Autodesk Fusion 360 part; units mm, degrees
(part 2 of 7)
sketch "Editable cross section (98)" plane through (0, 0, 0) normal (0, 0, 1) x (1, 0, 0) in component "left scoring bearing bridge 33"
  line L0 (-7.5, -5) -> (7.5, -5)
  line L1 (7.5, -5) -> (7.5, 5)
  line L2 (7.5, 5) -> (-7.5, 5)
  line L3 (-7.5, 5) -> (-7.5, -5)
extrude "Stock length''''''''''''''''''''''''''''''''''''''''''''''''''''''''''''''''''''''''''''" add sketch "Editable cross section (98)" along normal blind 42 separate body makes body 77 in component "left scoring bearing bridge 33"
sketch "Editable cross section (99)" plane through (0, 0, 0) normal (0, 0, 1) x (1, 0, 0) in component "left feed diverter pivot"
  circle A0 centre (0, 0) radius 7
extrude "Stock length'''''''''''''''''''''''''''''''''''''''''''''''''''''''''''''''''''''''''''''" add sketch "Editable cross section (99)" along normal blind 24 separate body makes body 78 in component "left feed diverter pivot"
sketch "Editable cross section (100)" plane through (0, 0, 0) normal (0, 0, 1) x (1, 0, 0) in component "right feed diverter pivot"
  circle A0 centre (0, 0) radius 7
extrude "Stock length''''''''''''''''''''''''''''''''''''''''''''''''''''''''''''''''''''''''''''''" add sketch "Editable cross section (100)" along normal blind 24 separate body makes body 79 in component "right feed diverter pivot"
sketch "Editable cross section (101)" plane through (0, 0, 0) normal (0, 0, 1) x (1, 0, 0) in component "feed diverter vane"
  line L0 (-2, -75) -> (2, -75)
  line L1 (2, -75) -> (2, 75)
  line L2 (2, 75) -> (-2, 75)
  line L3 (-2, 75) -> (-2, -75)
extrude "Stock length'''''''''''''''''''''''''''''''''''''''''''''''''''''''''''''''''''''''''''''''" add sketch "Editable cross section (101)" along normal blind 46 separate body makes body 80 in component "feed diverter vane"
sketch "Editable cross section (102)" plane through (0, 0, 0) normal (0, 0, 1) x (1, 0, 0) in component "front left public wheel"
  circle A0 centre (0, 0) radius 38.1
sketch "Editable cross section (103)" plane through (0, 0, 0) normal (0, 0, 1) x (1, 0, 0) in component "front left public drive housing"
  line L0 (-40, -40) -> (40, -40)
  line L1 (40, -40) -> (40, 40)
  line L2 (40, 40) -> (-40, 40)
  line L3 (-40, 40) -> (-40, -40)
sketch "Editable cross section (104)" plane through (0, 0, 0) normal (0, 0, 1) x (1, 0, 0) in component "front left public motor reserve"
  circle A0 centre (0, 0) radius 29.9
sketch "Editable cross section (105)" plane through (0, 0, 0) normal (0, 0, 1) x (1, 0, 0) in component "front right public wheel"
  circle A0 centre (0, 0) radius 38.1
sketch "Editable cross section (106)" plane through (0, 0, 0) normal (0, 0, 1) x (1, 0, 0) in component "front right public drive housing"
  line L0 (-40, -40) -> (40, -40)
  line L1 (40, -40) -> (40, 40)
  line L2 (40, 40) -> (-40, 40)
  line L3 (-40, 40) -> (-40, -40)
sketch "Editable cross section (107)" plane through (0, 0, 0) normal (0, 0, 1) x (1, 0, 0) in component "front right public motor reserve"
  circle A0 centre (0, 0) radius 29.9
sketch "Editable cross section (108)" plane through (0, 0, 0) normal (0, 0, 1) x (1, 0, 0) in component "rear left public wheel"
  circle A0 centre (0, 0) radius 38.1
sketch "Editable cross section (109)" plane through (0, 0, 0) normal (0, 0, 1) x (1, 0, 0) in component "rear left public drive housing"
  line L0 (-40, -40) -> (40, -40)
  line L1 (40, -40) -> (40, 40)
  line L2 (40, 40) -> (-40, 40)
  line L3 (-40, 40) -> (-40, -40)
sketch "Editable cross section (110)" plane through (0, 0, 0) normal (0, 0, 1) x (1, 0, 0) in component "rear left public motor reserve"
  circle A0 centre (0, 0) radius 29.9
sketch "Editable cross section (111)" plane through (0, 0, 0) normal (0, 0, 1) x (1, 0, 0) in component "rear right public wheel"
  circle A0 centre (0, 0) radius 38.1
sketch "Editable cross section (112)" plane through (0, 0, 0) normal (0, 0, 1) x (1, 0, 0) in component "rear right public drive housing"
  line L0 (-40, -40) -> (40, -40)
  line L1 (40, -40) -> (40, 40)
  line L2 (40, 40) -> (-40, 40)
  line L3 (-40, 40) -> (-40, -40)
sketch "Editable cross section (113)" plane through (0, 0, 0) normal (0, 0, 1) x (1, 0, 0) in component "rear right public motor reserve"
  circle A0 centre (0, 0) radius 29.9
sketch "Editable cross section (114)" plane through (0, 0, 0) normal (0, 0, 1) x (1, 0, 0) in component "right public scoring motor envelope"
  circle A0 centre (0, 0) radius 30
extrude "Stock length''''''''''''''''''''''''''''''''''''''''''''''''''''''''''''''''''''''''''''''''" add sketch "Editable cross section (114)" along normal blind 93.26 separate body makes body 81 in component "right public scoring motor envelope"
sketch "Editable cross section (115)" plane through (0, 0, 0) normal (0, 0, 1) x (1, 0, 0) in component "left public scoring motor envelope"
  circle A0 centre (0, 0) radius 30
extrude "Stock length'''''''''''''''''''''''''''''''''''''''''''''''''''''''''''''''''''''''''''''''''" add sketch "Editable cross section (115)" along normal blind 93.26 separate body makes body 82 in component "left public scoring motor envelope"
sketch "Editable cross section (116)" plane through (0, 0, 0) normal (0, 0, 1) x (1, 0, 0) in component "rear lift custody gate"
  line L0 (-2, -65) -> (2, -65)
  line L1 (2, -65) -> (2, 65)
  line L2 (2, 65) -> (-2, 65)
  line L3 (-2, 65) -> (-2, -65)
extrude "Stock length''''''''''''''''''''''''''''''''''''''''''''''''''''''''''''''''''''''''''''''''''" add sketch "Editable cross section (116)" along normal blind 416 separate body makes body 83 in component "rear lift custody gate"
sketch "Editable cross section (117)" plane through (0, 0, 0) normal (0, 0, 1) x (1, 0, 0) in component "front lift custody guide"
  line L0 (-2, -65) -> (2, -65)
  line L1 (2, -65) -> (2, 65)
  line L2 (2, 65) -> (-2, 65)
  line L3 (-2, 65) -> (-2, -65)
extrude "Stock length'''''''''''''''''''''''''''''''''''''''''''''''''''''''''''''''''''''''''''''''''''" add sketch "Editable cross section (117)" along normal blind 361 separate body makes body 84 in component "front lift custody guide"
sketch "Editable cross section (118)" plane through (0, 0, 0) normal (0, 0, 1) x (1, 0, 0) in component "left mast"
  line L0 (-10, -10) -> (10, -10)
  line L1 (10, -10) -> (10, 10)
  line L2 (10, 10) -> (-10, 10)
  line L3 (-10, 10) -> (-10, -10)
  line L4 (-8, -8) -> (8, -8)
  line L5 (8, -8) -> (8, 8)
  line L6 (8, 8) -> (-8, 8)
  line L7 (-8, 8) -> (-8, -8)
extrude "Stock length''''''''''''''''''''''''''''''''''''''''''''''''''''''''''''''''''''''''''''''''''''" add sketch "Editable cross section (118)" along normal blind 629.2 separate body makes body 85 in component "left mast"
sketch "Editable cross section (119)" plane through (0, 0, 0) normal (0, 0, 1) x (1, 0, 0) in component "left aft mast"
  line L0 (-10, -10) -> (10, -10)
  line L1 (10, -10) -> (10, 10)
  line L2 (10, 10) -> (-10, 10)
  line L3 (-10, 10) -> (-10, -10)
  line L4 (-8, -8) -> (8, -8)
  line L5 (8, -8) -> (8, 8)
  line L6 (8, 8) -> (-8, 8)
  line L7 (-8, 8) -> (-8, -8)
extrude "Stock length'''''''''''''''''''''''''''''''''''''''''''''''''''''''''''''''''''''''''''''''''''''" add sketch "Editable cross section (119)" along normal blind 629.2 separate body makes body 86 in component "left aft mast"
sketch "Editable cross section (120)" plane through (0, 0, 0) normal (0, 0, 1) x (1, 0, 0) in component "left upper bearing plate"
  line L0 (-64, -19) -> (64, -19)
  line L1 (64, -19) -> (64, 19)
  line L2 (64, 19) -> (-64, 19)
  line L3 (-64, 19) -> (-64, -19)
extrude "Stock length''''''''''''''''''''''''''''''''''''''''''''''''''''''''''''''''''''''''''''''''''''''" add sketch "Editable cross section (120)" along normal blind 6 separate body makes body 87 in component "left upper bearing plate"
sketch "Editable cross section (121)" plane through (0, 0, 0) normal (0, 0, 1) x (1, 0, 0) in component "left lower bearing plate"
  line L0 (-27, -21.5) -> (27, -21.5)
  line L1 (27, -21.5) -> (27, 21.5)
  line L2 (27, 21.5) -> (-27, 21.5)
  line L3 (-27, 21.5) -> (-27, -21.5)
extrude "Stock length'''''''''''''''''''''''''''''''''''''''''''''''''''''''''''''''''''''''''''''''''''''''" add sketch "Editable cross section (121)" along normal blind 6 separate body makes body 88 in component "left lower bearing plate"
sketch "Editable cross section (122)" plane through (0, 0, 0) normal (0, 0, 1) x (1, 0, 0) in component "left lead screw envelope"
  circle A0 centre (0, 0) radius 5
extrude "Stock length''''''''''''''''''''''''''''''''''''''''''''''''''''''''''''''''''''''''''''''''''''''''" add sketch "Editable cross section (122)" along normal blind 187 separate body makes body 89 in component "left lead screw envelope"
sketch "Editable cross section (123)" plane through (0, 0, 0) normal (0, 0, 1) x (1, 0, 0) in component "left lift motor envelope"
  circle A0 centre (0, 0) radius 30
extrude "Stock length'''''''''''''''''''''''''''''''''''''''''''''''''''''''''''''''''''''''''''''''''''''''''" add sketch "Editable cross section (123)" along normal blind 61 separate body makes body 90 in component "left lift motor envelope"
sketch "Editable cross section (124)" plane through (0, 0, 0) normal (0, 0, 1) x (1, 0, 0) in component "left reduction envelope"
  line L0 (-19, -32) -> (19, -32)
  line L1 (19, -32) -> (19, 32)
  line L2 (19, 32) -> (-19, 32)
  line L3 (-19, 32) -> (-19, -32)
extrude "Stock length''''''''''''''''''''''''''''''''''''''''''''''''''''''''''''''''''''''''''''''''''''''''''" add sketch "Editable cross section (124)" along normal blind 20 separate body makes body 91 in component "left reduction envelope"
sketch "Editable cross section (125)" plane through (0, 0, 0) normal (0, 0, 1) x (1, 0, 0) in component "left driven nut"
  line L0 (-9, -9.5) -> (9, -9.5)
  line L1 (9, -9.5) -> (9, 9.5)
  line L2 (9, 9.5) -> (-9, 9.5)
  line L3 (-9, 9.5) -> (-9, -9.5)
  circle A0 centre (0, -0.5) radius 5
extrude "Stock length'''''''''''''''''''''''''''''''''''''''''''''''''''''''''''''''''''''''''''''''''''''''''''" add sketch "Editable cross section (125)" along normal blind 14 separate body makes body 92 in component "left driven nut"
sketch "Editable cross section (126)" plane through (0, 0, 0) normal (0, 0, 1) x (1, 0, 0) in component "left nut link"
  line L0 (-8, -8) -> (8, -8)
  line L1 (8, -8) -> (8, 8)
  line L2 (8, 8) -> (-8, 8)
  line L3 (-8, 8) -> (-8, -8)
  circle A0 centre (0, -1) radius 5.8
extrude "Stock length''''''''''''''''''''''''''''''''''''''''''''''''''''''''''''''''''''''''''''''''''''''''''''" add sketch "Editable cross section (126)" along normal blind 10 separate body makes body 93 in component "left nut link"
sketch "Editable cross section (127)" plane through (0, 0, 0) normal (0, 0, 1) x (1, 0, 0) in component "left crosshead cheek"
  line L0 (-87.5, -11.5) -> (87.5, -11.5)
  line L1 (87.5, -11.5) -> (87.5, 11.5)
  line L2 (87.5, 11.5) -> (-87.5, 11.5)
  line L3 (-87.5, 11.5) -> (-87.5, -11.5)
  circle A0 centre (-35.5, 1.5) radius 5.8
extrude "Stock length'''''''''''''''''''''''''''''''''''''''''''''''''''''''''''''''''''''''''''''''''''''''''''''" add sketch "Editable cross section (127)" along normal blind 14 separate body makes body 94 in component "left crosshead cheek"
sketch "Editable cross section (128)" plane through (0, 0, 0) normal (0, 0, 1) x (1, 0, 0) in component "left forward carriage sleeve"
  line L0 (-13, -12.5) -> (13, -12.5)
  line L1 (13, -12.5) -> (13, 12.5)
  line L2 (13, 12.5) -> (-13, 12.5)
  line L3 (-13, 12.5) -> (-13, -12.5)
  line L4 (-11, -10.5) -> (11, -10.5)
  line L5 (11, -10.5) -> (11, 10.5)
  line L6 (11, 10.5) -> (-11, 10.5)
  line L7 (-11, 10.5) -> (-11, -10.5)
extrude "Stock length''''''''''''''''''''''''''''''''''''''''''''''''''''''''''''''''''''''''''''''''''''''''''''''" add sketch "Editable cross section (128)" along normal blind 40 separate body makes body 95 in component "left forward carriage sleeve"
sketch "Editable cross section (129)" plane through (0, 0, 0) normal (0, 0, 1) x (1, 0, 0) in component "left aft carriage sleeve"
  line L0 (-13, -12.5) -> (13, -12.5)
  line L1 (13, -12.5) -> (13, 12.5)
  line L2 (13, 12.5) -> (-13, 12.5)
  line L3 (-13, 12.5) -> (-13, -12.5)
  line L4 (-11, -10.5) -> (11, -10.5)
  line L5 (11, -10.5) -> (11, 10.5)
  line L6 (11, 10.5) -> (-11, 10.5)
  line L7 (-11, 10.5) -> (-11, -10.5)
extrude "Stock length'''''''''''''''''''''''''''''''''''''''''''''''''''''''''''''''''''''''''''''''''''''''''''''''" add sketch "Editable cross section (129)" along normal blind 40 separate body makes body 96 in component "left aft carriage sleeve"
sketch "Editable cross section (130)" plane through (0, 0, 0) normal (0, 0, 1) x (1, 0, 0) in component "left extension sleeve"
  line L0 (-14, -15) -> (14, -15)
  line L1 (14, -15) -> (14, 15)
  line L2 (14, 15) -> (-14, 15)
  line L3 (-14, 15) -> (-14, -15)
  line L4 (-12, -13) -> (12, -13)
  line L5 (12, -13) -> (12, 13)
  line L6 (12, 13) -> (-12, 13)
  line L7 (-12, 13) -> (-12, -13)
extrude "Stock length''''''''''''''''''''''''''''''''''''''''''''''''''''''''''''''''''''''''''''''''''''''''''''''''" add sketch "Editable cross section (130)" along normal blind 87 separate body makes body 97 in component "left extension sleeve"
sketch "Editable cross section (131)" plane through (0, 0, 0) normal (0, 0, 1) x (1, 0, 0) in component "left sleeve pedestal"
  line L0 (-11, -11) -> (11, -11)
  line L1 (11, -11) -> (11, 11)
  line L2 (11, 11) -> (-11, 11)
  line L3 (-11, 11) -> (-11, -11)
extrude "Stock length'''''''''''''''''''''''''''''''''''''''''''''''''''''''''''''''''''''''''''''''''''''''''''''''''" add sketch "Editable cross section (131)" along normal blind 23 separate body makes body 98 in component "left sleeve pedestal"
sketch "Editable cross section (132)" plane through (0, 0, 0) normal (0, 0, 1) x (1, 0, 0) in component "left extending rail"
  line L0 (-10, -11) -> (10, -11)
  line L1 (10, -11) -> (10, 11)
  line L2 (10, 11) -> (-10, 11)
  line L3 (-10, 11) -> (-10, -11)
  line L4 (-8, -9) -> (8, -9)
  line L5 (8, -9) -> (8, 9)
  line L6 (8, 9) -> (-8, 9)
  line L7 (-8, 9) -> (-8, -9)
extrude "Stock length''''''''''''''''''''''''''''''''''''''''''''''''''''''''''''''''''''''''''''''''''''''''''''''''''" add sketch "Editable cross section (132)" along normal blind 395 separate body makes body 99 in component "left extending rail"
sketch "Low-rung crown and capture slot" plane through (0, 0, 0) normal (0, 0, 1) x (1, 0, 0) in component "left crown hook"
  line L0 (-283, 710) -> (-271, 710)
  line L1 (-271, 710) -> (-271, 737)
  line L2 (-271, 737) -> (-223, 737)
  line L3 (-223, 737) -> (-223, 710)
  line L4 (-223, 710) -> (-211, 710)
  line L5 (-211, 710) -> (-211, 736)
  line L6 (-211, 736) -> (-176, 736)
  line L7 (-176, 736) -> (-176, 753)
  line L8 (-176, 753) -> (-283, 753)
  line L9 (-283, 753) -> (-283, 710)
extrude "Hook plate thickness" add sketch "Low-rung crown and capture slot" along normal blind 12 separate body makes body 100 in component "left crown hook"
sketch "Editable cross section (133)" plane through (0, 0, 0) normal (0, 0, 1) x (1, 0, 0) in component "right mast"
  line L0 (-10, -10) -> (10, -10)
  line L1 (10, -10) -> (10, 10)
  line L2 (10, 10) -> (-10, 10)
  line L3 (-10, 10) -> (-10, -10)
  line L4 (-8, -8) -> (8, -8)
  line L5 (8, -8) -> (8, 8)
  line L6 (8, 8) -> (-8, 8)
  line L7 (-8, 8) -> (-8, -8)
extrude "Stock length'''''''''''''''''''''''''''''''''''''''''''''''''''''''''''''''''''''''''''''''''''''''''''''''''''" add sketch "Editable cross section (133)" along normal blind 629.2 separate body makes body 101 in component "right mast"
sketch "Editable cross section (134)" plane through (0, 0, 0) normal (0, 0, 1) x (1, 0, 0) in component "right aft mast"
  line L0 (-10, -10) -> (10, -10)
  line L1 (10, -10) -> (10, 10)
  line L2 (10, 10) -> (-10, 10)
  line L3 (-10, 10) -> (-10, -10)
  line L4 (-8, -8) -> (8, -8)
  line L5 (8, -8) -> (8, 8)
  line L6 (8, 8) -> (-8, 8)
  line L7 (-8, 8) -> (-8, -8)
extrude "Stock length''''''''''''''''''''''''''''''''''''''''''''''''''''''''''''''''''''''''''''''''''''''''''''''''''''" add sketch "Editable cross section (134)" along normal blind 629.2 separate body makes body 102 in component "right aft mast"
sketch "Editable cross section (135)" plane through (0, 0, 0) normal (0, 0, 1) x (1, 0, 0) in component "right upper bearing plate"
  line L0 (-64, -19) -> (64, -19)
  line L1 (64, -19) -> (64, 19)
  line L2 (64, 19) -> (-64, 19)
  line L3 (-64, 19) -> (-64, -19)
extrude "Stock length'''''''''''''''''''''''''''''''''''''''''''''''''''''''''''''''''''''''''''''''''''''''''''''''''''''" add sketch "Editable cross section (135)" along normal blind 6 separate body makes body 103 in component "right upper bearing plate"
sketch "Editable cross section (136)" plane through (0, 0, 0) normal (0, 0, 1) x (1, 0, 0) in component "right lower bearing plate"
  line L0 (-27, -21.5) -> (27, -21.5)
  line L1 (27, -21.5) -> (27, 21.5)
  line L2 (27, 21.5) -> (-27, 21.5)
  line L3 (-27, 21.5) -> (-27, -21.5)
extrude "Stock length''''''''''''''''''''''''''''''''''''''''''''''''''''''''''''''''''''''''''''''''''''''''''''''''''''''" add sketch "Editable cross section (136)" along normal blind 6 separate body makes body 104 in component "right lower bearing plate"
sketch "Editable cross section (137)" plane through (0, 0, 0) normal (0, 0, 1) x (1, 0, 0) in component "right lead screw envelope"
  circle A0 centre (0, 0) radius 5
extrude "Stock length'''''''''''''''''''''''''''''''''''''''''''''''''''''''''''''''''''''''''''''''''''''''''''''''''''''''" add sketch "Editable cross section (137)" along normal blind 187 separate body makes body 105 in component "right lead screw envelope"
sketch "Editable cross section (138)" plane through (0, 0, 0) normal (0, 0, 1) x (1, 0, 0) in component "right lift motor envelope"
  circle A0 centre (0, 0) radius 30
extrude "Stock length''''''''''''''''''''''''''''''''''''''''''''''''''''''''''''''''''''''''''''''''''''''''''''''''''''''''" add sketch "Editable cross section (138)" along normal blind 61 separate body makes body 106 in component "right lift motor envelope"
sketch "Editable cross section (139)" plane through (0, 0, 0) normal (0, 0, 1) x (1, 0, 0) in component "right reduction envelope"
  line L0 (-19, -32) -> (19, -32)
  line L1 (19, -32) -> (19, 32)
  line L2 (19, 32) -> (-19, 32)
  line L3 (-19, 32) -> (-19, -32)
extrude "Stock length'''''''''''''''''''''''''''''''''''''''''''''''''''''''''''''''''''''''''''''''''''''''''''''''''''''''''" add sketch "Editable cross section (139)" along normal blind 20 separate body makes body 107 in component "right reduction envelope"
sketch "Editable cross section (140)" plane through (0, 0, 0) normal (0, 0, 1) x (1, 0, 0) in component "right driven nut"
  line L0 (-9, -9.5) -> (9, -9.5)
  line L1 (9, -9.5) -> (9, 9.5)
  line L2 (9, 9.5) -> (-9, 9.5)
  line L3 (-9, 9.5) -> (-9, -9.5)
  circle A0 centre (0, 0.5) radius 5
extrude "Stock length''''''''''''''''''''''''''''''''''''''''''''''''''''''''''''''''''''''''''''''''''''''''''''''''''''''''''" add sketch "Editable cross section (140)" along normal blind 14 separate body makes body 108 in component "right driven nut"
sketch "Editable cross section (141)" plane through (0, 0, 0) normal (0, 0, 1) x (1, 0, 0) in component "right nut link"
  line L0 (-8, -8) -> (8, -8)
  line L1 (8, -8) -> (8, 8)
  line L2 (8, 8) -> (-8, 8)
  line L3 (-8, 8) -> (-8, -8)
  circle A0 centre (0, 1) radius 5.8
extrude "Stock length'''''''''''''''''''''''''''''''''''''''''''''''''''''''''''''''''''''''''''''''''''''''''''''''''''''''''''" add sketch "Editable cross section (141)" along normal blind 10 separate body makes body 109 in component "right nut link"
sketch "Editable cross section (142)" plane through (0, 0, 0) normal (0, 0, 1) x (1, 0, 0) in component "right crosshead cheek"
  line L0 (-87.5, -11.5) -> (87.5, -11.5)
  line L1 (87.5, -11.5) -> (87.5, 11.5)
  line L2 (87.5, 11.5) -> (-87.5, 11.5)
  line L3 (-87.5, 11.5) -> (-87.5, -11.5)
  circle A0 centre (-35.5, -1.5) radius 5.8
extrude "Stock length''''''''''''''''''''''''''''''''''''''''''''''''''''''''''''''''''''''''''''''''''''''''''''''''''''''''''''" add sketch "Editable cross section (142)" along normal blind 14 separate body makes body 110 in component "right crosshead cheek"
sketch "Editable cross section (143)" plane through (0, 0, 0) normal (0, 0, 1) x (1, 0, 0) in component "right forward carriage sleeve"
  line L0 (-13, -12.5) -> (13, -12.5)
  line L1 (13, -12.5) -> (13, 12.5)
  line L2 (13, 12.5) -> (-13, 12.5)
  line L3 (-13, 12.5) -> (-13, -12.5)
  line L4 (-11, -10.5) -> (11, -10.5)
  line L5 (11, -10.5) -> (11, 10.5)
  line L6 (11, 10.5) -> (-11, 10.5)
  line L7 (-11, 10.5) -> (-11, -10.5)
extrude "Stock length'''''''''''''''''''''''''''''''''''''''''''''''''''''''''''''''''''''''''''''''''''''''''''''''''''''''''''''" add sketch "Editable cross section (143)" along normal blind 40 separate body makes body 111 in component "right forward carriage sleeve"
sketch "Editable cross section (144)" plane through (0, 0, 0) normal (0, 0, 1) x (1, 0, 0) in component "right aft carriage sleeve"
  line L0 (-13, -12.5) -> (13, -12.5)
  line L1 (13, -12.5) -> (13, 12.5)
  line L2 (13, 12.5) -> (-13, 12.5)
  line L3 (-13, 12.5) -> (-13, -12.5)
  line L4 (-11, -10.5) -> (11, -10.5)
  line L5 (11, -10.5) -> (11, 10.5)
  line L6 (11, 10.5) -> (-11, 10.5)
  line L7 (-11, 10.5) -> (-11, -10.5)
extrude "Stock length''''''''''''''''''''''''''''''''''''''''''''''''''''''''''''''''''''''''''''''''''''''''''''''''''''''''''''''" add sketch "Editable cross section (144)" along normal blind 40 separate body makes body 112 in component "right aft carriage sleeve"
sketch "Editable cross section (145)" plane through (0, 0, 0) normal (0, 0, 1) x (1, 0, 0) in component "right extension sleeve"
  line L0 (-14, -15) -> (14, -15)
  line L1 (14, -15) -> (14, 15)
  line L2 (14, 15) -> (-14, 15)
  line L3 (-14, 15) -> (-14, -15)
  line L4 (-12, -13) -> (12, -13)
  line L5 (12, -13) -> (12, 13)
  line L6 (12, 13) -> (-12, 13)
  line L7 (-12, 13) -> (-12, -13)
extrude "Stock length'''''''''''''''''''''''''''''''''''''''''''''''''''''''''''''''''''''''''''''''''''''''''''''''''''''''''''''''" add sketch "Editable cross section (145)" along normal blind 87 separate body makes body 113 in component "right extension sleeve"
sketch "Editable cross section (146)" plane through (0, 0, 0) normal (0, 0, 1) x (1, 0, 0) in component "right sleeve pedestal"
  line L0 (-11, -11) -> (11, -11)
  line L1 (11, -11) -> (11, 11)
  line L2 (11, 11) -> (-11, 11)
  line L3 (-11, 11) -> (-11, -11)
extrude "Stock length''''''''''''''''''''''''''''''''''''''''''''''''''''''''''''''''''''''''''''''''''''''''''''''''''''''''''''''''" add sketch "Editable cross section (146)" along normal blind 23 separate body makes body 114 in component "right sleeve pedestal"
sketch "Editable cross section (147)" plane through (0, 0, 0) normal (0, 0, 1) x (1, 0, 0) in component "right extending rail"
  line L0 (-10, -11) -> (10, -11)
  line L1 (10, -11) -> (10, 11)
  line L2 (10, 11) -> (-10, 11)
  line L3 (-10, 11) -> (-10, -11)
  line L4 (-8, -9) -> (8, -9)
  line L5 (8, -9) -> (8, 9)
  line L6 (8, 9) -> (-8, 9)
  line L7 (-8, 9) -> (-8, -9)
extrude "Stock length'''''''''''''''''''''''''''''''''''''''''''''''''''''''''''''''''''''''''''''''''''''''''''''''''''''''''''''''''" add sketch "Editable cross section (147)" along normal blind 395 separate body makes body 115 in component "right extending rail"
sketch "Low-rung crown and capture slot (2)" plane through (0, 0, 0) normal (0, 0, 1) x (1, 0, 0) in component "right crown hook"
  line L0 (-283, 710) -> (-271, 710)
  line L1 (-271, 710) -> (-271, 737)
  line L2 (-271, 737) -> (-223, 737)
  line L3 (-223, 737) -> (-223, 710)
  line L4 (-223, 710) -> (-211, 710)
  line L5 (-211, 710) -> (-211, 736)
  line L6 (-211, 736) -> (-176, 736)
  line L7 (-176, 736) -> (-176, 753)
  line L8 (-176, 753) -> (-283, 753)
  line L9 (-283, 753) -> (-283, 710)
extrude "Hook plate thickness'" add sketch "Low-rung crown and capture slot (2)" along normal blind 12 separate body makes body 116 in component "right crown hook"
sketch "Editable cross section (148)" plane through (0, 0, 0) normal (0, 0, 1) x (1, 0, 0) in component "crosshead lift bridge"
  line L0 (-10, -10) -> (10, -10)
  line L1 (10, -10) -> (10, 10)
  line L2 (10, 10) -> (-10, 10)
  line L3 (-10, 10) -> (-10, -10)
  line L4 (-8, -8) -> (8, -8)
  line L5 (8, -8) -> (8, 8)
  line L6 (8, 8) -> (-8, 8)
  line L7 (-8, 8) -> (-8, -8)
extrude "Stock length''''''''''''''''''''''''''''''''''''''''''''''''''''''''''''''''''''''''''''''''''''''''''''''''''''''''''''''''''" add sketch "Editable cross section (148)" along normal blind 630 separate body makes body 117 in component "crosshead lift bridge"
sketch "Editable cross section (149)" plane through (0, 0, 0) normal (0, 0, 1) x (1, 0, 0) in component "rail synchronizing tie"
  line L0 (-10, -82) -> (10, -82)
  line L1 (10, -82) -> (10, 82)
  line L2 (10, 82) -> (-10, 82)
  line L3 (-10, 82) -> (-10, -82)
extrude "Stock length'''''''''''''''''''''''''''''''''''''''''''''''''''''''''''''''''''''''''''''''''''''''''''''''''''''''''''''''''''" add sketch "Editable cross section (149)" along normal blind 4 separate body makes body 118 in component "rail synchronizing tie"
sketch "Editable cross section (150)" plane through (0, 0, 0) normal (0, 0, 1) x (1, 0, 0) in component "extension bearing beam"
  line L0 (-193, -14) -> (193, -14)
  line L1 (193, -14) -> (193, 14)
  line L2 (193, 14) -> (-193, 14)
  line L3 (-193, 14) -> (-193, -14)
extrude "Stock length''''''''''''''''''''''''''''''''''''''''''''''''''''''''''''''''''''''''''''''''''''''''''''''''''''''''''''''''''''" add sketch "Editable cross section (150)" along normal blind 15 separate body makes body 119 in component "extension bearing beam"
sketch "Editable cross section (151)" plane through (0, 0, 0) normal (0, 0, 1) x (1, 0, 0) in component "extension rear bearing and stop"
  line L0 (-14, -17) -> (14, -17)
  line L1 (14, -17) -> (14, 17)
  line L2 (14, 17) -> (-14, 17)
  line L3 (-14, 17) -> (-14, -17)
  circle A0 centre (0, 0) radius 5.2
extrude "Stock length'''''''''''''''''''''''''''''''''''''''''''''''''''''''''''''''''''''''''''''''''''''''''''''''''''''''''''''''''''''" add sketch "Editable cross section (151)" along normal blind 12 separate body makes body 120 in component "extension rear bearing and stop"
sketch "Editable cross section (152)" plane through (0, 0, 0) normal (0, 0, 1) x (1, 0, 0) in component "extension forward bearing"
  line L0 (-14, -17) -> (14, -17)
  line L1 (14, -17) -> (14, 17)
  line L2 (14, 17) -> (-14, 17)
  line L3 (-14, 17) -> (-14, -17)
  circle A0 centre (0, 0) radius 5.2
extrude "Stock length''''''''''''''''''''''''''''''''''''''''''''''''''''''''''''''''''''''''''''''''''''''''''''''''''''''''''''''''''''''" add sketch "Editable cross section (152)" along normal blind 12 separate body makes body 121 in component "extension forward bearing"
sketch "Editable cross section (153)" plane through (0, 0, 0) normal (0, 0, 1) x (1, 0, 0) in component "extension screw envelope"
  circle A0 centre (0, 0) radius 5
extrude "Stock length'''''''''''''''''''''''''''''''''''''''''''''''''''''''''''''''''''''''''''''''''''''''''''''''''''''''''''''''''''''''" add sketch "Editable cross section (153)" along normal blind 279 separate body makes body 122 in component "extension screw envelope"
sketch "Editable cross section (154)" plane through (0, 0, 0) normal (0, 0, 1) x (1, 0, 0) in component "extension deployment nut"
  line L0 (-10, -13) -> (10, -13)
  line L1 (10, -13) -> (10, 13)
  line L2 (10, 13) -> (-10, 13)
  line L3 (-10, 13) -> (-10, -13)
  circle A0 centre (0, 0) radius 5
extrude "Stock length''''''''''''''''''''''''''''''''''''''''''''''''''''''''''''''''''''''''''''''''''''''''''''''''''''''''''''''''''''''''" add sketch "Editable cross section (154)" along normal blind 20 separate body makes body 123 in component "extension deployment nut"
sketch "Editable cross section (155)" plane through (0, 0, 0) normal (0, 0, 1) x (1, 0, 0) in component "extension nut hanger"
  line L0 (-10, -8) -> (10, -8)
  line L1 (10, -8) -> (10, 8)
  line L2 (10, 8) -> (-10, 8)
  line L3 (-10, 8) -> (-10, -8)
extrude "Stock length'''''''''''''''''''''''''''''''''''''''''''''''''''''''''''''''''''''''''''''''''''''''''''''''''''''''''''''''''''''''''" add sketch "Editable cross section (155)" along normal blind 4 separate body makes body 124 in component "extension nut hanger"
sketch "Editable cross section (156)" plane through (0, 0, 0) normal (0, 0, 1) x (1, 0, 0) in component "extension motor envelope"
  circle A0 centre (0, 0) radius 18
extrude "Stock length''''''''''''''''''''''''''''''''''''''''''''''''''''''''''''''''''''''''''''''''''''''''''''''''''''''''''''''''''''''''''" add sketch "Editable cross section (156)" along normal blind 49 separate body makes body 125 in component "extension motor envelope"
sketch "Editable cross section (157)" plane through (0, 0, 0) normal (0, 0, 1) x (1, 0, 0) in component "extension motor foot"
  line L0 (-8, -9) -> (8, -9)
  line L1 (8, -9) -> (8, 9)
  line L2 (8, 9) -> (-8, 9)
  line L3 (-8, 9) -> (-8, -9)
extrude "Stock length'''''''''''''''''''''''''''''''''''''''''''''''''''''''''''''''''''''''''''''''''''''''''''''''''''''''''''''''''''''''''''" add sketch "Editable cross section (157)" along normal blind 2 separate body makes body 126 in component "extension motor foot"
ref_plane "WorkPlane1" through (0, -25.4, 0) normal (0, 1, 0) x (0, 0, 1) in component "rear perimeter tube"
sketch "New stock profile" plane through (0, -25.4, 0) normal (0, 1, 0) x (1, 0, 0) in component "rear perimeter tube"
  line L0 (12.7, 0) -> (-12.7, 0)
  line L1 (-12.7, 0) -> (-12.7, -629.2)
  line L2 (-12.7, -629.2) -> (12.7, -629.2)
  line L3 (12.7, -629.2) -> (12.7, 0)
extrude "New 1" add sketch "New stock profile" along normal blind 50.8 separate body makes body 127 in component "rear perimeter tube"
ref_plane "WorkPlane2" through (0, -22.225, 0) normal (0, 1, 0) x (0, 0, 1) in component "rear perimeter tube"
sketch "Cut stock profile" plane through (0, -22.225, 0) normal (0, 1, 0) x (1, 0, 0) in component "rear perimeter tube"
  line L0 (9.525, 1) -> (-9.525, 1)
  line L1 (-9.525, 1) -> (-9.525, -630.2)
  line L2 (-9.525, -630.2) -> (9.525, -630.2)
  line L3 (9.525, -630.2) -> (9.525, 1)
ref_plane "WorkPlane3" through (-9.2, 0, 0) normal (1, 0, 0) x (0, 1, 0) in component "rear perimeter tube"
sketch "Cut stock profile (1)" plane through (-9.2, 0, 0) normal (1, 0, 0) x (0, 0, -1) in component "rear perimeter tube"
  circle A0 centre (-509.75, -5.3) radius 6.55
ref_plane "WorkPlane4" through (-9.2, 0, 0) normal (1, 0, 0) x (0, 1, 0) in component "rear perimeter tube"
sketch "Cut stock profile (2)" plane through (-9.2, 0, 0) normal (1, 0, 0) x (0, 0, -1) in component "rear perimeter tube"
  circle A0 centre (-509.75, 15.7) radius 6.55
ref_plane "WorkPlane5" through (-9.2, 0, 0) normal (1, 0, 0) x (0, 1, 0) in component "rear perimeter tube"
sketch "Cut stock profile (3)" plane through (-9.2, 0, 0) normal (1, 0, 0) x (0, 0, -1) in component "rear perimeter tube"
  circle A0 centre (-119.45, -5.3) radius 6.55
ref_plane "WorkPlane6" through (-9.2, 0, 0) normal (1, 0, 0) x (0, 1, 0) in component "rear perimeter tube"
sketch "Cut stock profile (4)" plane through (-9.2, 0, 0) normal (1, 0, 0) x (0, 0, -1) in component "rear perimeter tube"
  circle A0 centre (-119.45, 15.7) radius 6.55
ref_plane "WorkPlane1" through (0, -25.4, 0) normal (0, 1, 0) x (0, 0, 1) in component "right perimeter tube"
sketch "New stock profile (2)" plane through (0, -25.4, 0) normal (0, 1, 0) x (1, 0, 0) in component "right perimeter tube"
  line L0 (-12.7, 0) -> (-12.7, -680)
  line L1 (-12.7, -680) -> (12.7, -680)
  line L2 (12.7, -680) -> (12.7, 0)
  line L3 (12.7, 0) -> (-12.7, 0)
extrude "New 1'" add sketch "New stock profile (2)" along normal blind 50.8 separate body makes body 128 in component "right perimeter tube"
ref_plane "WorkPlane2" through (0, -22.225, 0) normal (0, 1, 0) x (0, 0, 1) in component "right perimeter tube"
sketch "Cut stock profile (5)" plane through (0, -22.225, 0) normal (0, 1, 0) x (1, 0, 0) in component "right perimeter tube"
  line L0 (-9.525, 1) -> (-9.525, -681)
  line L1 (-9.525, -681) -> (9.525, -681)
  line L2 (9.525, -681) -> (9.525, 1)
  line L3 (9.525, 1) -> (-9.525, 1)
extrude "Cut 2" cut sketch "Cut stock profile (5)" along normal blind 44.45 bodies 128 in component "right perimeter tube"
extrude "Extrude2" [no effect] in component "right blue front bumper"
extrude "Extrude2'" [no effect] in component "rear blue bumper"
ref_plane "WorkPlane3" through (9.2, 0, 0) normal (1, 0, 0) x (0, 1, 0) in component "right perimeter tube"
sketch "Cut stock profile (1) (2)" plane through (9.2, 0, 0) normal (1, 0, 0) x (0, 0, -1) in component "right perimeter tube"
  circle A0 centre (-535.15, -5.3) radius 6.55
ref_plane "WorkPlane4" through (9.2, 0, 0) normal (1, 0, 0) x (0, 1, 0) in component "right perimeter tube"
sketch "Cut stock profile (2) (2)" plane through (9.2, 0, 0) normal (1, 0, 0) x (0, 0, -1) in component "right perimeter tube"
  circle A0 centre (-535.15, 15.7) radius 6.55
ref_plane "WorkPlane5" through (9.2, 0, 0) normal (1, 0, 0) x (0, 1, 0) in component "right perimeter tube"
sketch "Cut stock profile (3) (2)" plane through (9.2, 0, 0) normal (1, 0, 0) x (0, 0, -1) in component "right perimeter tube"
  circle A0 centre (-144.85, -5.3) radius 6.55
ref_plane "WorkPlane6" through (9.2, 0, 0) normal (1, 0, 0) x (0, 1, 0) in component "right perimeter tube"
sketch "Cut stock profile (4) (2)" plane through (9.2, 0, 0) normal (1, 0, 0) x (0, 0, -1) in component "right perimeter tube"
  circle A0 centre (-144.85, 15.7) radius 6.55
ref_plane "WorkPlane1" through (0, -25.4, 0) normal (0, 1, 0) x (0, 0, 1) in component "right front return"
sketch "New stock profile (3)" plane through (0, -25.4, 0) normal (0, 1, 0) x (1, 0, 0) in component "right front return"
  line L0 (12.7, 0) -> (-12.7, 0)
  line L1 (-12.7, 0) -> (-12.7, -164.6)
  line L2 (-12.7, -164.6) -> (12.7, -164.6)
  line L3 (12.7, -164.6) -> (12.7, 0)
extrude "New 1''" add sketch "New stock profile (3)" along normal blind 50.8 separate body makes body 129 in component "right front return"
ref_plane "WorkPlane2" through (0, -22.225, 0) normal (0, 1, 0) x (0, 0, 1) in component "right front return"
sketch "Cut stock profile (6)" plane through (0, -22.225, 0) normal (0, 1, 0) x (1, 0, 0) in component "right front return"
  line L0 (9.525, 1) -> (-9.525, 1)
  line L1 (-9.525, 1) -> (-9.525, -165.6)
  line L2 (-9.525, -165.6) -> (9.525, -165.6)
  line L3 (9.525, -165.6) -> (9.525, 1)
extrude "Cut 2 (1)" [suppressed] in component "right perimeter tube"
extrude "Extrude3" cut sketch "Cut stock profile (6)" along normal blind 44.45 bodies 129 in component "right front return"
ref_plane "WorkPlane3" through (9.2, 0, 0) normal (1, 0, 0) x (0, 1, 0) in component "right front return"
sketch "Cut stock profile (1) (3)" plane through (9.2, 0, 0) normal (1, 0, 0) x (0, 0, -1) in component "right front return"
  circle A0 centre (-119.45, -5.3) radius 6.55
ref_plane "WorkPlane4" through (9.2, 0, 0) normal (1, 0, 0) x (0, 1, 0) in component "right front return"
sketch "Cut stock profile (2) (3)" plane through (9.2, 0, 0) normal (1, 0, 0) x (0, 0, -1) in component "right front return"
  circle A0 centre (-119.45, 15.7) radius 6.55
ref_plane "WorkPlane1" through (0, -16.05, 0) normal (0, 1, 0) x (0, 0, 1) in component "right floor sill"
sketch "New stock profile (4)" plane through (0, -16.05, 0) normal (0, 1, 0) x (1, 0, 0) in component "right floor sill"
  line L0 (2.475, 0) -> (2.475, -480)
  line L1 (2.475, -480) -> (21.525, -480)
  line L2 (21.525, -480) -> (21.525, 0)
  line L3 (21.525, 0) -> (2.475, 0)
extrude "New 1'''" add sketch "New stock profile (4)" along normal blind 19.05 separate body makes body 130 in component "right floor sill"
ref_plane "WorkPlane2" through (0, -14.4752, 0) normal (0, 1, 0) x (0, 0, 1) in component "right floor sill"
sketch "Cut stock profile (7)" plane through (0, -14.4752, 0) normal (0, 1, 0) x (1, 0, 0) in component "right floor sill"
  line L0 (4.0498, 1) -> (4.0498, -481)
  line L1 (4.0498, -481) -> (19.9502, -481)
  line L2 (19.9502, -481) -> (19.9502, 1)
  line L3 (19.9502, 1) -> (4.0498, 1)
ref_plane "WorkPlane1" through (0, 0, 7) normal (0, 0, 1) x (1, 0, 0) in component "rear right hopper post"
sketch "New stock profile (5)" plane through (0, 0, 7) normal (0, 0, 1) x (1, 0, 0) in component "rear right hopper post"
  line L0 (27.475, 2.475) -> (46.525, 2.475)
  line L1 (46.525, 2.475) -> (46.525, 21.525)
  line L2 (46.525, 21.525) -> (27.475, 21.525)
  line L3 (27.475, 21.525) -> (27.475, 2.475)
extrude "New 1''''" add sketch "New stock profile (5)" along normal blind 88.95 separate body makes body 131 in component "rear right hopper post"
ref_plane "WorkPlane2" through (0, 0, 6) normal (0, 0, 1) x (1, 0, 0) in component "rear right hopper post"
sketch "Cut stock profile (8)" plane through (0, 0, 6) normal (0, 0, 1) x (1, 0, 0) in component "rear right hopper post"
  line L0 (29.0498, 4.0498) -> (44.9502, 4.0498)
  line L1 (44.9502, 4.0498) -> (44.9502, 19.9502)
  line L2 (44.9502, 19.9502) -> (29.0498, 19.9502)
  line L3 (29.0498, 19.9502) -> (29.0498, 4.0498)
extrude "Cut 2'" cut sketch "Cut stock profile (8)" along normal blind 90.95 bodies 131 in component "rear right hopper post"
extrude "Extrude4" [no effect] in component "right floor sill"
ref_plane "WorkPlane1" through (0, 0, 7) normal (0, 0, 1) x (1, 0, 0) in component "front right hopper post"
sketch "New stock profile (6)" plane through (0, 0, 7) normal (0, 0, 1) x (1, 0, 0) in component "front right hopper post"
  line L0 (-56.525, 2.475) -> (-37.475, 2.475)
  line L1 (-37.475, 2.475) -> (-37.475, 21.525)
  line L2 (-37.475, 21.525) -> (-56.525, 21.525)
  line L3 (-56.525, 21.525) -> (-56.525, 2.475)
extrude "New 1'''''" add sketch "New stock profile (6)" along normal blind 88.95 separate body makes body 132 in component "front right hopper post"
ref_plane "WorkPlane2" through (0, 0, 6) normal (0, 0, 1) x (1, 0, 0) in component "front right hopper post"
sketch "Cut stock profile (9)" plane through (0, 0, 6) normal (0, 0, 1) x (1, 0, 0) in component "front right hopper post"
  line L0 (-54.9502, 4.0498) -> (-39.0498, 4.0498)
  line L1 (-39.0498, 4.0498) -> (-39.0498, 19.9502)
  line L2 (-39.0498, 19.9502) -> (-54.9502, 19.9502)
  line L3 (-54.9502, 19.9502) -> (-54.9502, 4.0498)
extrude "Cut 2''" cut sketch "Cut stock profile (9)" along normal blind 90.95 bodies 132 in component "front right hopper post"
extrude "Extrude5" [no effect] in component "right floor sill"
ref_plane "WorkPlane1" through (0, -25.4, 0) normal (0, 1, 0) x (0, 0, 1) in component "left perimeter tube"
sketch "New stock profile (7)" plane through (0, -25.4, 0) normal (0, 1, 0) x (1, 0, 0) in component "left perimeter tube"
  line L0 (-12.7, 0) -> (-12.7, -680)
  line L1 (-12.7, -680) -> (12.7, -680)
  line L2 (12.7, -680) -> (12.7, 0)
  line L3 (12.7, 0) -> (-12.7, 0)
extrude "New 1''''''" add sketch "New stock profile (7)" along normal blind 50.8 separate body makes body 133 in component "left perimeter tube"
ref_plane "WorkPlane2" through (0, -22.225, 0) normal (0, 1, 0) x (0, 0, 1) in component "left perimeter tube"
sketch "Cut stock profile (10)" plane through (0, -22.225, 0) normal (0, 1, 0) x (1, 0, 0) in component "left perimeter tube"
  line L0 (-9.525, 1) -> (-9.525, -681)
  line L1 (-9.525, -681) -> (9.525, -681)
  line L2 (9.525, -681) -> (9.525, 1)
  line L3 (9.525, 1) -> (-9.525, 1)
extrude "Cut 2'''" cut sketch "Cut stock profile (10)" along normal blind 44.45 bodies 133 in component "left perimeter tube"
extrude "Extrude2''" [no effect] in component "left blue front bumper"
extrude "Extrude3'" [no effect] in component "rear blue bumper"
ref_plane "WorkPlane3" through (-9.2, 0, 0) normal (1, 0, 0) x (0, 1, 0) in component "left perimeter tube"
sketch "Cut stock profile (1) (4)" plane through (-9.2, 0, 0) normal (1, 0, 0) x (0, 0, -1) in component "left perimeter tube"
  circle A0 centre (-535.15, -5.3) radius 6.55
ref_plane "WorkPlane4" through (-9.2, 0, 0) normal (1, 0, 0) x (0, 1, 0) in component "left perimeter tube"
sketch "Cut stock profile (2) (4)" plane through (-9.2, 0, 0) normal (1, 0, 0) x (0, 0, -1) in component "left perimeter tube"
  circle A0 centre (-535.15, 15.7) radius 6.55
ref_plane "WorkPlane5" through (-9.2, 0, 0) normal (1, 0, 0) x (0, 1, 0) in component "left perimeter tube"
sketch "Cut stock profile (3) (3)" plane through (-9.2, 0, 0) normal (1, 0, 0) x (0, 0, -1) in component "left perimeter tube"
  circle A0 centre (-144.85, -5.3) radius 6.55
ref_plane "WorkPlane6" through (-9.2, 0, 0) normal (1, 0, 0) x (0, 1, 0) in component "left perimeter tube"
sketch "Cut stock profile (4) (3)" plane through (-9.2, 0, 0) normal (1, 0, 0) x (0, 0, -1) in component "left perimeter tube"
  circle A0 centre (-144.85, 15.7) radius 6.55
ref_plane "WorkPlane1" through (0, -25.4, 0) normal (0, 1, 0) x (0, 0, 1) in component "left front return"
sketch "New stock profile (8)" plane through (0, -25.4, 0) normal (0, 1, 0) x (1, 0, 0) in component "left front return"
  line L0 (12.7, 0) -> (-12.7, 0)
  line L1 (-12.7, 0) -> (-12.7, -164.6)
  line L2 (-12.7, -164.6) -> (12.7, -164.6)
  line L3 (12.7, -164.6) -> (12.7, 0)
extrude "New 1'''''''" add sketch "New stock profile (8)" along normal blind 50.8 separate body makes body 134 in component "left front return"
ref_plane "WorkPlane2" through (0, -22.225, 0) normal (0, 1, 0) x (0, 0, 1) in component "left front return"
sketch "Cut stock profile (11)" plane through (0, -22.225, 0) normal (0, 1, 0) x (1, 0, 0) in component "left front return"
  line L0 (9.525, 1) -> (-9.525, 1)
  line L1 (-9.525, 1) -> (-9.525, -165.6)
  line L2 (-9.525, -165.6) -> (9.525, -165.6)
  line L3 (9.525, -165.6) -> (9.525, 1)
extrude "Cut 2 (1)'" [suppressed] in component "left perimeter tube"
extrude "Extrude3''" cut sketch "Cut stock profile (11)" along normal blind 44.45 bodies 134 in component "left front return"
ref_plane "WorkPlane3" through (9.2, 0, 0) normal (1, 0, 0) x (0, 1, 0) in component "left front return"
sketch "Cut stock profile (1) (5)" plane through (9.2, 0, 0) normal (1, 0, 0) x (0, 0, -1) in component "left front return"
  circle A0 centre (-45.15, -5.3) radius 6.55
ref_plane "WorkPlane4" through (9.2, 0, 0) normal (1, 0, 0) x (0, 1, 0) in component "left front return"
sketch "Cut stock profile (2) (5)" plane through (9.2, 0, 0) normal (1, 0, 0) x (0, 0, -1) in component "left front return"
  circle A0 centre (-45.15, 15.7) radius 6.55
ref_plane "WorkPlane1" through (0, -16.05, 0) normal (0, 1, 0) x (0, 0, 1) in component "left floor sill"
sketch "New stock profile (9)" plane through (0, -16.05, 0) normal (0, 1, 0) x (1, 0, 0) in component "left floor sill"
  line L0 (-21.525, 0) -> (-21.525, -480)
  line L1 (-21.525, -480) -> (-2.475, -480)
  line L2 (-2.475, -480) -> (-2.475, 0)
  line L3 (-2.475, 0) -> (-21.525, 0)
extrude "New 1''''''''" add sketch "New stock profile (9)" along normal blind 19.05 separate body makes body 135 in component "left floor sill"
ref_plane "WorkPlane2" through (0, -14.4752, 0) normal (0, 1, 0) x (0, 0, 1) in component "left floor sill"
sketch "Cut stock profile (12)" plane through (0, -14.4752, 0) normal (0, 1, 0) x (1, 0, 0) in component "left floor sill"
  line L0 (-19.9502, 1) -> (-19.9502, -481)
  line L1 (-19.9502, -481) -> (-4.0498, -481)
  line L2 (-4.0498, -481) -> (-4.0498, 1)
  line L3 (-4.0498, 1) -> (-19.9502, 1)
ref_plane "WorkPlane1" through (0, 0, 7) normal (0, 0, 1) x (1, 0, 0) in component "rear left hopper post"
sketch "New stock profile (10)" plane through (0, 0, 7) normal (0, 0, 1) x (1, 0, 0) in component "rear left hopper post"
  line L0 (27.475, -21.525) -> (46.525, -21.525)
  line L1 (46.525, -21.525) -> (46.525, -2.475)
  line L2 (46.525, -2.475) -> (27.475, -2.475)
  line L3 (27.475, -2.475) -> (27.475, -21.525)
extrude "New 1'''''''''" add sketch "New stock profile (10)" along normal blind 88.95 separate body makes body 136 in component "rear left hopper post"
ref_plane "WorkPlane2" through (0, 0, 6) normal (0, 0, 1) x (1, 0, 0) in component "rear left hopper post"
sketch "Cut stock profile (13)" plane through (0, 0, 6) normal (0, 0, 1) x (1, 0, 0) in component "rear left hopper post"
  line L0 (29.0498, -19.9502) -> (44.9502, -19.9502)
  line L1 (44.9502, -19.9502) -> (44.9502, -4.0498)
  line L2 (44.9502, -4.0498) -> (29.0498, -4.0498)
  line L3 (29.0498, -4.0498) -> (29.0498, -19.9502)
extrude "Cut 2''''" cut sketch "Cut stock profile (13)" along normal blind 90.95 bodies 136 in component "rear left hopper post"
extrude "Extrude4'" [no effect] in component "left floor sill"
ref_plane "WorkPlane1" through (0, 0, 7) normal (0, 0, 1) x (1, 0, 0) in component "front left hopper post"
sketch "New stock profile (11)" plane through (0, 0, 7) normal (0, 0, 1) x (1, 0, 0) in component "front left hopper post"
  line L0 (-56.525, -21.525) -> (-37.475, -21.525)
  line L1 (-37.475, -21.525) -> (-37.475, -2.475)
  line L2 (-37.475, -2.475) -> (-56.525, -2.475)
  line L3 (-56.525, -2.475) -> (-56.525, -21.525)
extrude "New 1''''''''''" add sketch "New stock profile (11)" along normal blind 88.95 separate body makes body 137 in component "front left hopper post"
ref_plane "WorkPlane2" through (0, 0, 6) normal (0, 0, 1) x (1, 0, 0) in component "front left hopper post"
sketch "Cut stock profile (14)" plane through (0, 0, 6) normal (0, 0, 1) x (1, 0, 0) in component "front left hopper post"
  line L0 (-54.9502, -19.9502) -> (-39.0498, -19.9502)
  line L1 (-39.0498, -19.9502) -> (-39.0498, -4.0498)
  line L2 (-39.0498, -4.0498) -> (-54.9502, -4.0498)
  line L3 (-54.9502, -4.0498) -> (-54.9502, -19.9502)
extrude "Cut 2'''''" cut sketch "Cut stock profile (14)" along normal blind 90.95 bodies 137 in component "front left hopper post"
extrude "Extrude5'" [no effect] in component "left floor sill"
ref_plane "WorkPlane1" through (0, -16.4, 0) normal (0, 1, 0) x (0, 0, 1) in component "rear deck crossmember"
sketch "New stock profile (12)" plane through (0, -16.4, 0) normal (0, 1, 0) x (1, 0, 0) in component "rear deck crossmember"
  line L0 (-24.3, -6.75) -> (-49.7, -6.75)
  line L1 (-49.7, -6.75) -> (-49.7, -623.25)
  line L2 (-49.7, -623.25) -> (-24.3, -623.25)
  line L3 (-24.3, -623.25) -> (-24.3, -6.75)
extrude "New 1'''''''''''" add sketch "New stock profile (12)" along normal blind 25.4 separate body makes body 138 in component "rear deck crossmember"
ref_plane "WorkPlane2" through (0, -13.225, 0) normal (0, 1, 0) x (0, 0, 1) in component "rear deck crossmember"
sketch "Cut stock profile (15)" plane through (0, -13.225, 0) normal (0, 1, 0) x (1, 0, 0) in component "rear deck crossmember"
  line L0 (-27.475, -5.75) -> (-46.525, -5.75)
  line L1 (-46.525, -5.75) -> (-46.525, -624.25)
  line L2 (-46.525, -624.25) -> (-27.475, -624.25)
  line L3 (-27.475, -624.25) -> (-27.475, -5.75)
extrude "Cut 2''''''" cut sketch "Cut stock profile (15)" along normal blind 19.05 bodies 138 in component "rear deck crossmember"
ref_plane "WorkPlane1" through (0, 0, 65.5) normal (0, 0, 1) x (1, 0, 0) in component "rear right crossmember backing plate"
sketch "New stock profile (13)" plane through (0, 0, 65.5) normal (0, 0, 1) x (1, 0, 0) in component "rear right crossmember backing plate"
  line L0 (-176.4, -314.6) -> (-125.6, -314.6)
  line L1 (-125.6, -314.6) -> (-125.6, -308.25)
  line L2 (-125.6, -308.25) -> (-176.4, -308.25)
  line L3 (-176.4, -308.25) -> (-176.4, -314.6)
extrude "New 1''''''''''''" add sketch "New stock profile (13)" along normal blind 63.5 separate body makes body 139 in component "rear right crossmember backing plate"
ref_plane "WorkPlane1" through (0, 0, 65.5) normal (0, 0, 1) x (1, 0, 0) in component "rear left crossmember backing plate"
sketch "New stock profile (14)" plane through (0, 0, 65.5) normal (0, 0, 1) x (1, 0, 0) in component "rear left crossmember backing plate"
  line L0 (-176.4, 308.25) -> (-125.6, 308.25)
  line L1 (-125.6, 308.25) -> (-125.6, 314.6)
  line L2 (-125.6, 314.6) -> (-176.4, 314.6)
  line L3 (-176.4, 314.6) -> (-176.4, 308.25)
extrude "New 1'''''''''''''" add sketch "New stock profile (14)" along normal blind 63.5 separate body makes body 140 in component "rear left crossmember backing plate"
ref_plane "WorkPlane1" through (0, -16.4, 0) normal (0, 1, 0) x (0, 0, 1) in component "front deck crossmember"
sketch "New stock profile (15)" plane through (0, -16.4, 0) normal (0, 1, 0) x (1, 0, 0) in component "front deck crossmember"
  line L0 (59.7, -6.75) -> (34.3, -6.75)
  line L1 (34.3, -6.75) -> (34.3, -623.25)
  line L2 (34.3, -623.25) -> (59.7, -623.25)
  line L3 (59.7, -623.25) -> (59.7, -6.75)
extrude "New 1''''''''''''''" add sketch "New stock profile (15)" along normal blind 25.4 separate body makes body 141 in component "front deck crossmember"
ref_plane "WorkPlane2" through (0, -13.225, 0) normal (0, 1, 0) x (0, 0, 1) in component "front deck crossmember"
sketch "Cut stock profile (16)" plane through (0, -13.225, 0) normal (0, 1, 0) x (1, 0, 0) in component "front deck crossmember"
  line L0 (56.525, -5.75) -> (37.475, -5.75)
  line L1 (37.475, -5.75) -> (37.475, -624.25)
  line L2 (37.475, -624.25) -> (56.525, -624.25)
  line L3 (56.525, -624.25) -> (56.525, -5.75)
extrude "Cut 2'''''''" cut sketch "Cut stock profile (16)" along normal blind 19.05 bodies 141 in component "front deck crossmember"